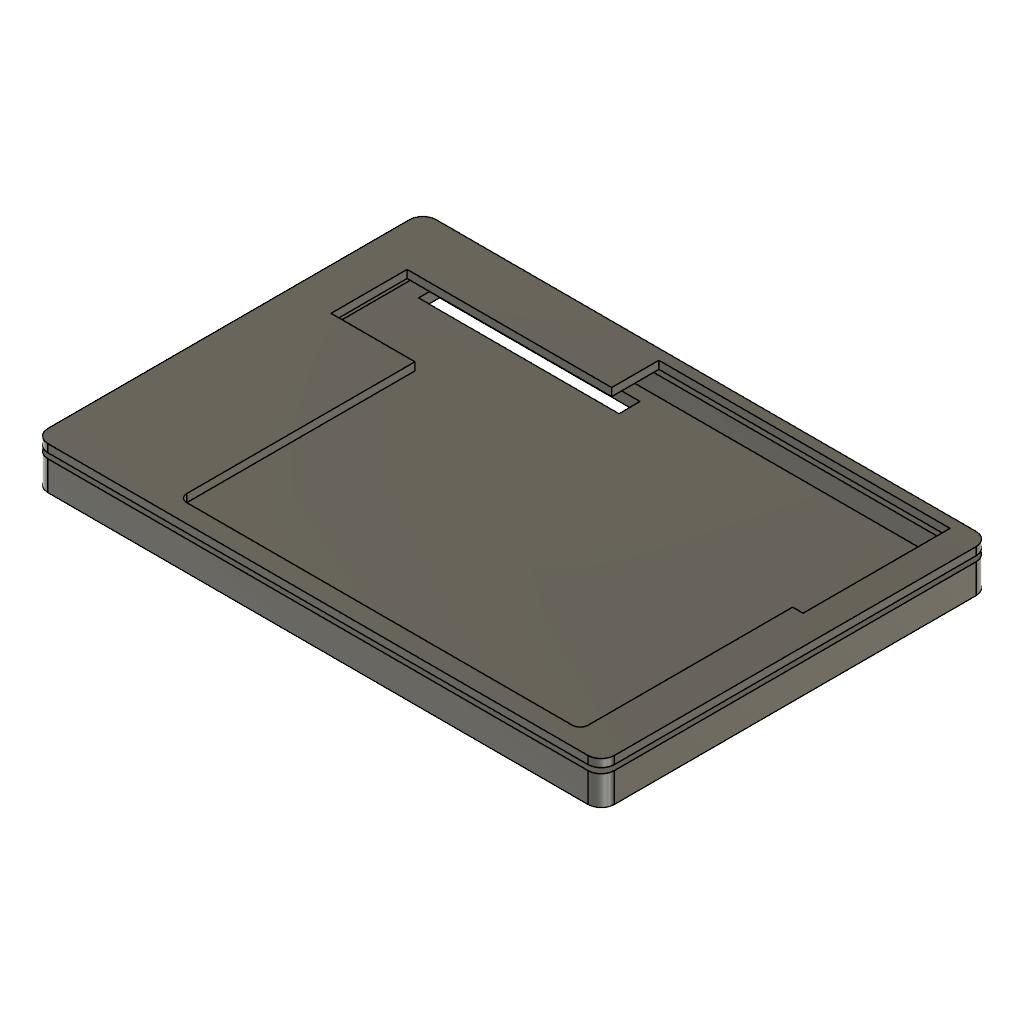
case (Autodesk Fusion 360 design; units mm, degrees)
part number: 2026-10-25-17-18-47-838
Autodesk Fusion 360 part; units mm, degrees
derive "DerivedContext1"
sketch "sketch 395" plane through (0, 0, 0) normal (0, 0, 1) x (1, 0, 0)
  line L0 (-52, -22) -> (52, -22)
  line L1 (52, -22) -> (52, 52)
  line L2 (52, 52) -> (-52, 52)
  line L3 (-52, 52) -> (-52, -22)
  circle A0 centre (48, -18) radius 1.2
  circle A1 centre (-48, 48) radius 1.2
  circle A2 centre (-48, -18) radius 1.2
  line L4 (-50, -20) -> (50, -20)
  line L5 (50, -20) -> (50, 50)
  line L6 (50, 50) -> (-50, 50)
  line L7 (-50, 50) -> (-50, -20)
  line L8 (-46.25, -18) -> (-46.25, -20)
  line L9 (-48, -16.25) -> (-50, -16.25)
  arc A3 (-46.25, -18) -> (-48, -16.25) centre (-48, -18) ccw
  line L10 (46.25, -18) -> (46.25, -20)
  line L11 (48, -16.25) -> (50, -16.25)
  arc A4 (48, -16.25) -> (46.25, -18) centre (48, -18) ccw
  line L12 (-48, 46.25) -> (-50, 46.25)
  line L13 (-46.25, 48) -> (-46.25, 50)
  arc A5 (-48, 46.25) -> (-46.25, 48) centre (-48, 48) ccw
  line L14 (46, 50) -> (50, 50)
  line L15 (50, 50) -> (50, 46)
  line L16 (50, 46) -> (46, 46)
  line L17 (46, 46) -> (46, 50)
  line L18 (-50, 50) -> (-46.3, 50)
  line L19 (-50, 47.5) -> (-50, 50)
  line L20 (-46.3, 47.5) -> (-8.1, 47.5)
  line L21 (-8.1, 47.5) -> (-8.1, 43.5)
  line L22 (-8.1, 43.5) -> (-46.3, 43.5)
  line L23 (-46.3, 43.5) -> (-46.3, 47.5)
extrude "Extrude1" add sketch "sketch 395" against normal blind 2 contours L0 L1 L2 L3 | A0 | A1 | A2 | L4 L7 L8 L9 A3 | L4 L5 L6 L7 L8 L9 A3 L10 L11 A4 L12 L13 A5 L16 L17 | L4 L5 L10 L11 A4 | L6 L7 L12 L13 A5 L18 L19 | L5 L6 L14 L15 L16 L17 | L20 L21 L22 L23 makes body 1
extrude "Extrude2" add sketch "sketch 395" along normal blind 4 contours L0 L1 L2 L3 bodies 1
extrude "Extrude3" add sketch "sketch 395" along normal blind 2 contours L4 L7 L8 L9 A3 bodies 1
extrude "Extrude4" add sketch "sketch 395" along normal blind 2 contours L6 L7 L12 L13 A5 L18 L19 bodies 1
extrude "Extrude5" add sketch "sketch 395" along normal blind 2 contours L4 L5 L10 L11 A4 bodies 1
extrude "Extrude6" add sketch "sketch 395" along normal blind 2 contours L5 L6 L14 L15 L16 L17 bodies 1
fillet "Fillet1" radius 2 1 edges at (46, 46, 1) on bodies 1
extrude "Extrude7" cut sketch "sketch 395" against normal blind 2 contours L20 L21 L22 L23 bodies 1
extrude "Extrude8" cut 1 faces at (-16.6667, -21.3333, 4) along direction (0, 0, -1) blind 0.4 on bodies 1 bodies 1
extrude "Extrude9" add 1 faces at (-16.6667, -21.3333, 3.6) along direction (0, 0, 1) blind 1 separate body on bodies 1 makes body 2
move_body "Move1" bodies 2 to x (1, 0, 0) y (0, 1, 0) z (0, 0, 1) at (0, 0, 1)
extrude "Extrude10" add 1 faces at (-52, 27.3333, -0.1333) along direction (-1, 0, 0) blind 2 on bodies 1 bodies 1
extrude "Extrude11" add 1 faces at (52, 2.6667, -0.1333) along direction (1, 0, 0) blind 2 on bodies 1 bodies 1
extrude "Extrude12" add 1 faces at (-52, 27.3333, 4.9333) along direction (-1, 0, 0) blind 2 on bodies 2 bodies 2
extrude "Extrude13" add 1 faces at (52, 2.6667, 4.9333) along direction (1, 0, 0) blind 2 on bodies 2 bodies 2
extrude "Extrude14" add 1 faces at (-50, 3.3333, 4.9333) along direction (1, 0, 0) blind 4 on bodies 2 bodies 2
box "BoxPrimitive1" add length 1 width 2 height 9 placed x (0, 0, -1) y (1, 0, 0) z (0, -1, 0) at (-46, 50, 5.6) bodies 2
extrude "Extrude15" add 1 faces at (-44, 47, 4.9333) along direction (1, 0, 0) blind 30 on bodies 2 bodies 2
extrude "Extrude16" add 1 faces at (-14, 47, 4.9333) along direction (1, 0, 0) blind 7 on bodies 2 bodies 2
extrude "Extrude17" add 1 faces at (18, -20, 4.9333) along direction (0, 1, 0) blind 1.5 on bodies 2 bodies 2
extrude "Extrude18" add 1 faces at (50, 27.1667, 4.9333) along direction (-1, 0, 0) blind 1.5 on bodies 2 bodies 2
box "BoxPrimitive2" add length 1 width 3 height 45 placed x (0, 0, 1) y (1, 0, 0) z (0, 1, 0) at (-46, -18.5, 4.6) bodies 2
extrude "Extrude19" add 1 faces at (-43, -3.5, 5.2667) along direction (1, 0, 0) blind 10 on bodies 2 bodies 2
extrude "Extrude20" add 1 faces at (-33, -3.5, 5.2667) along direction (1, 0, 0) blind 3 on bodies 2 bodies 2
box "BoxPrimitive3" add length 1 width 10 height 2 placed x (0, 0, 1) y (0, 1, 0) z (-1, 0, 0) at (48.5, -18.5, 4.6) bodies 2
extrude "Extrude21" add 1 faces at (47.8333, -8.5, 5.2667) along direction (0, 1, 0) blind 30.5 on bodies 2 bodies 2
fillet "Fillet2" radius 1.5 2 edges at (46.5, -18.5, 5.1) (-30, -18.5, 5.1) on bodies 2
extrude "Extrude22" add 1 faces at (-43.3333, -4.1667, 5.6) along direction (0, 0, 1) blind 0.5 on bodies 2 bodies 2
fillet "Fillet3" radius 2.5 8 edges at (-54, -22, 0.8) (-54, 52, 0.8) (54, 52, 0.8) (54, -22, 0.8) (-54, -22, 5.35) (-54, 52, 5.35) (54, 52, 5.35) (54, -22, 5.35) on bodies 1 2
